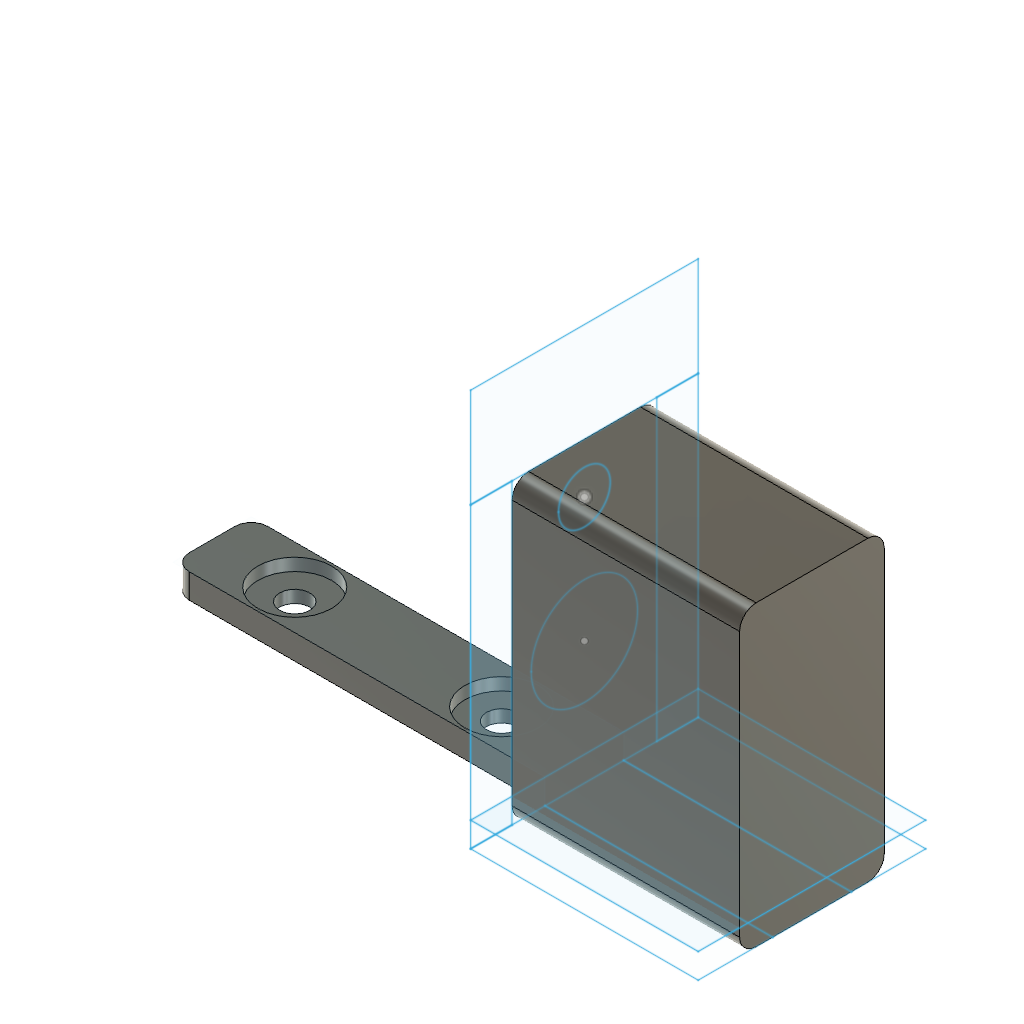
hotairblower (Autodesk Fusion 360 design; units mm, degrees)
part number: 2026-08-10-19-56-16-923
Autodesk Fusion 360 part; units mm, degrees
sketch "Sketch1" plane through (0, 0, 0) normal (0, 0, 1) x (1, 0, 0)
  line L0 (-28, 37) -> (62, 37)
  line L1 (62, 37) -> (62, 18)
  line L2 (62, 18) -> (-28, 18)
  line L3 (-28, 18) -> (-28, 37)
  dimension "d1" = 90
  dimension "d2" = 19
  constraint horizontal L0
  constraint vertical L1
  constraint horizontal L2
  constraint vertical L3
  measures "d1" distance of L0.start L0.end
  measures "d2" distance of L0.start L2.end
extrude "Extrude1" add sketch "Sketch1" along normal blind 6
sketch "Sketch2" plane through (0, 0, 6) normal (0, 0, 1) x (-1, 0, 0)
  line L0 (28, -37) -> (28, -18)
  line L1 (28, -18) -> (-62, -18)
  line L2 (-62, -18) -> (-62, -37)
  line L3 (-62, -37) -> (28, -37)
ref_plane "WorkPlane1" through (17, 27.5, 6) normal (0, 0, 1) x (-1, 0, 0)
sketch "Sketch3" plane through (0, 0, 6) normal (0, 0, 1) x (1, 0, 0)
  line L0 (17, 37) -> (17, 18)
  circle A0 centre (-8, 27.5) radius 8.9
  circle A1 centre (42, 27.5) radius 8.9
  circle A2 centre (-8, 27.5) radius 3.65
  circle A3 centre (42, 27.5) radius 3.65
  dimension "d13" = 17.8
  dimension "d14" = 17.8
  dimension "d15" = 7.3
  dimension "d16" = 7.3
  constraint vertical L0
  constraint concentric A0 A2
  constraint concentric A1 A3
  measures "d13" diameter of A0
  measures "d14" diameter of A1
  measures "d15" diameter of A2
  measures "d16" diameter of A3
extrude "Extrude2" cut sketch "Sketch3" against normal blind 7 contours A2 | A3
extrude "Extrude3" cut sketch "Sketch3" against normal blind 3
sketch "Sketch7" plane through (0, 0, 0) normal (0, 0, 1) x (1, 0, 0)
  line L0 (62, 37) -> (117, 37)
  line L1 (117, 37) -> (117, 18)
  line L2 (117, 18) -> (62, 18)
  line L3 (62, 18) -> (62, 37)
  line L4 (62, 37) -> (117, 37)
  line L5 (117, 37) -> (117, 55)
  line L6 (117, 55) -> (62, 55)
  line L7 (62, 55) -> (62, 37)
  line L8 (117, 18) -> (62, 18)
  line L9 (62, 18) -> (62, 0)
  line L10 (62, 0) -> (117, 0)
  line L11 (117, 0) -> (117, 18)
  dimension "d37" = 55
  dimension "d38" = 19
  dimension "d39" = 18
  dimension "d40" = 55
  dimension "d41" = 18
  constraint horizontal L0
  constraint vertical L1
  constraint horizontal L2
  constraint vertical L3
  constraint horizontal L4
  constraint vertical L5
  constraint horizontal L6
  constraint vertical L7
  constraint horizontal L8
  constraint vertical L9
  constraint horizontal L10
  constraint vertical L11
  measures "d37" distance of L0.start L0.end
  measures "d38" distance of L0.start L2.end
  measures "d39" distance of L0.start L6.end
  measures "d40" distance of L1.end L2.end
  measures "d41" distance of L1.end L10.end
extrude "Extrude7" add sketch "Sketch7" along normal blind 6
sketch "Sketch8" plane through (0, 0, 6) normal (0, 0, 1) x (-1, 0, 0)
  circle A0 centre (-42, -27.5) radius 8.9
  circle A1 centre (8, -27.5) radius 8.9
  line L0 (28, -18) -> (-62, -18)
  line L1 (-62, -18) -> (-62, 0)
  line L2 (-62, 0) -> (-117, 0)
  line L3 (-117, 0) -> (-117, -55)
  line L4 (-117, -55) -> (-62, -55)
  line L5 (-62, -55) -> (-62, -37)
  line L6 (-62, -37) -> (28, -37)
  line L7 (28, -37) -> (28, -18)
sketch "Sketch9" plane through (0, 0, 6) normal (0, 0, 1) x (-1, 0, 0)
  line L0 (-62, -55) -> (-117, -55)
  line L1 (-117, -55) -> (-117, 0)
  line L2 (-117, 0) -> (-62, 0)
  line L3 (-62, 0) -> (-62, -55)
  constraint horizontal L0
  constraint vertical L1
  constraint horizontal L2
  constraint vertical L3
extrude "Extrude8" add sketch "Sketch9" along normal blind 90
sketch "Sketch10" plane through (62, 0, 0) normal (-1, 0, 0) x (0, -1, 0)
  line L0 (-37, 0) -> (-37, 6)
  line L1 (-37, 6) -> (-18, 6)
  line L2 (-18, 6) -> (-18, 0)
  line L3 (-18, 0) -> (0, 0)
  line L4 (0, 0) -> (0, 96)
  line L5 (0, 96) -> (-55, 96)
  line L6 (-55, 96) -> (-55, 0)
  line L7 (-55, 0) -> (-37, 0)
  circle A0 centre (-27.5, 59.8738) radius 6.2
  circle A1 centre (-27.5, 29.7467) radius 12.85
  dimension "d48" = 12.4
  dimension "d50" = 25.7
  measures "d48" diameter of A0
  measures "d50" diameter of A1
extrude "Extrude9" cut sketch "Sketch10" against normal blind 49 contours A0 | A1
sketch "Sketch11" plane through (62, 0, 0) normal (-1, 0, 0) x (0, -1, 0)
sketch "Sketch12" plane through (62, 0, 0) normal (-1, 0, 0) x (0, -1, 0)
  line L0 (-55, 96) -> (0, 96)
  line L1 (0, 96) -> (0, 72)
  line L2 (0, 72) -> (-55, 72)
  line L3 (-55, 72) -> (-55, 96)
  constraint horizontal L0
  constraint vertical L1
  constraint horizontal L2
  constraint vertical L3
extrude "Extrude10" cut sketch "Sketch12" against normal blind 60
sketch "Sketch13" plane through (62, 0, 0) normal (-1, 0, 0) x (0, -1, 0)
  line L0 (-55, 72) -> (-45, 72)
  line L1 (-45, 72) -> (-45, 0)
  line L2 (-45, 0) -> (-55, 0)
  line L3 (-55, 0) -> (-55, 72)
  line L4 (0, 72) -> (-10, 72)
  line L5 (-10, 72) -> (-10, 0)
  line L6 (-10, 0) -> (0, 0)
  line L7 (0, 0) -> (0, 72)
  dimension "d55" = 10
  dimension "d56" = 72
  dimension "d57" = 10
  dimension "d58" = 72
  constraint horizontal L0
  constraint vertical L1
  constraint horizontal L2
  constraint vertical L3
  constraint horizontal L4
  constraint vertical L5
  constraint horizontal L6
  constraint vertical L7
  measures "d55" distance of L0.start L0.end
  measures "d56" distance of L0.start L2.end
  measures "d57" distance of L4.start L4.end
  measures "d58" distance of L4.start L6.end
extrude "Extrude11" cut sketch "Sketch13" against normal blind 60
fillet "Fillet3" radius 4 2 edges at (89.5, 10, 72) (89.5, 45, 72)
fillet "Fillet4" radius 4 2 edges at (89.5, 45, 0) (89.5, 10, 0)
fillet "Fillet5" radius 4 2 edges at (-28, 37, 3) (-28, 18, 3)
sketch "Sketch14" plane through (62, 0, 0) normal (-1, 0, 0) x (0, -1, 0)
  circle A0 centre (-27.5, 59.8738) radius 6.3
  dimension "d67" = 12.6
  measures "d67" diameter of A0
extrude "Extrude12" cut sketch "Sketch14" against normal blind 49
